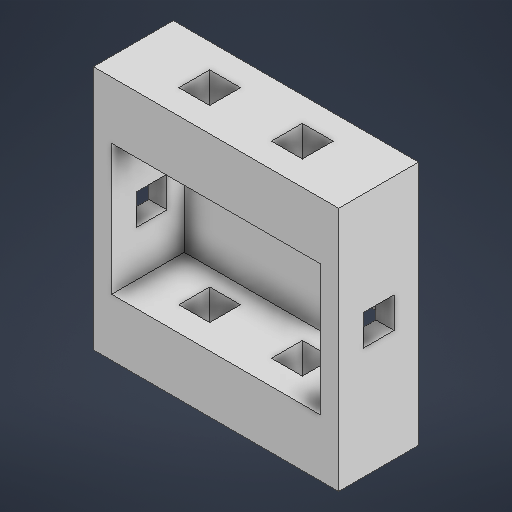
# Autodesk Inventor part: DOLNA
Saved by Autodesk Inventor 2026.1 (Build 301233020, 233B)
## iProperties
Created: 2026-09-25
Part Number: DOLNA
Material: Ogólny
Document SubType Name: Modeling
Designer: Bronh
Density: 1 g/cm^3
Appearance: Domyślna
Author: Bronh
Autodesk Inventor part; units mm, degrees
ref_plane "YZ Plane" through (0, 0, 0) normal (1, 0, 0) x (0, 1, 0)
ref_plane "XZ Plane" through (0, 0, 0) normal (0, 1, 0) x (-1, 0, 0)
ref_plane "XY Plane" through (0, 0, 0) normal (0, 0, 1) x (1, 0, 0)
sketch "Szkic1" plane through (0, 0, 0) normal (0, 0, 1) x (1, 0, 0)
  line L0 (0, 0) -> (135, 0)
  line L1 (135, 0) -> (135, 135)
  line L2 (135, 135) -> (0, 135)
  line L3 (0, 135) -> (0, 0)
  dimension "d0" = 135
  dimension "d1" = 135
  constraints: 8 end point, 2 parallel, 1 horizontal, 1 perpendicular
  measures "d0" distance of L2.end L1.end
  measures "d1" distance of L1.end L0.end
extrude "Wyciągnięcie proste1" add sketch "Szkic1" along normal blind 44
sketch "Szkic2" plane through (0, 0, 44) normal (0, 0, 1) x (1, 0, 0)
  line L0 (125, 103.5) -> (10, 103.5)
  line L1 (10, 103.5) -> (10, 31.5)
  line L2 (10, 31.5) -> (125, 31.5)
  line L3 (125, 31.5) -> (125, 103.5)
  line L4 (0, 135) -> (0, 0) projected
  line L5 (135, 135) -> (0, 135) projected
  dimension "d4" = 115
  dimension "d5" = 72
  dimension "d6" = 10
  dimension "d7" = 31.5
  constraints: 8 end point, 2 parallel, 1 horizontal, 1 perpendicular
  measures "d4" distance of L2.end L1.end
  measures "d5" distance of L1.end L0.end
  measures "d6" distance between parallel lines of L4 L1
  measures "d7" distance between parallel lines of L5 L0
extrude "Wyciągnięcie proste2" cut sketch "Szkic2" against normal blind 40
sketch "Szkic3" plane through (0, 0, 4) normal (0, 0, 1) x (1, 0, 0)
  line L0 (120, 56.5) -> (100, 56.5)
  line L1 (100, 56.5) -> (100, 36.5)
  line L2 (100, 36.5) -> (120, 36.5)
  line L3 (120, 36.5) -> (120, 56.5)
  line L4 (125, 31.5) -> (10, 31.5) projected
  line L5 (125, 103.5) -> (125, 31.5) projected
  point P0 (0, 0)
  dimension "d10" = 20
  dimension "d11" = 20
  dimension "d12" = 5
  dimension "d13" = 5
  constraints: 8 end point, 2 parallel, 1 horizontal, 1 perpendicular
  measures "d10" distance of L2.end L1.end
  measures "d11" distance of L1.end L0.end
  measures "d12" distance between parallel lines of L4 L2
  measures "d13" distance between parallel lines of L5 L3
extrude "Wyciągnięcie proste3" cut sketch "Szkic3" against normal blind 5
sketch "Szkic4" plane through (0, 0, 0) normal (0, -1, 0) x (1, 0, 0)
  line L0 (33.5, 30.5) -> (50.5, 30.5)
  line L1 (50.5, 30.5) -> (50.5, 13.5)
  line L2 (50.5, 13.5) -> (33.5, 13.5)
  line L3 (33.5, 13.5) -> (33.5, 30.5)
  line L4 (0, 44) -> (135, 44) projected
  line L5 (0, 0) -> (0, 44) projected
  point P0 (42, 30.5)
  point P1 (33.5, 22)
  dimension "d16" = 17
  dimension "d17" = 17
  dimension "d18" = 13.5
  dimension "d24" = 33.5
  constraints: 8 end point, 2 midpoint, 2 parallel, 1 horizontal, 1 perpendicular
  measures "d16" distance of L1.end L2.end
  measures "d17" distance of L0.end L1.end
  measures "d18" distance from line of point (42, 30.5) L4
  measures "d24" distance from line of L5 point (33.5, 22)
extrude "Wyciągnięcie proste4" cut sketch "Szkic4" against normal blind 31.5
sketch "Szkic7" plane through (135, 0, 0) normal (1, 0, 0) x (0, 0, -1)
  line L0 (-30.5, 61.5) -> (-13.5, 61.5)
  line L1 (-13.5, 61.5) -> (-13.5, 78.5)
  line L2 (-13.5, 78.5) -> (-30.5, 78.5)
  line L3 (-30.5, 78.5) -> (-30.5, 61.5)
  line L4 (0, 135) -> (-44, 135) projected
  line L5 (-44, 135) -> (-44, 0) projected
  point P0 (0, 0)
  point P1 (-22, 78.5)
  dimension "d30" = 17
  dimension "d31" = 17
  dimension "d32" = 56.5
  dimension "d41" = 13.5
  constraints: 8 end point, 2 parallel, 1 horizontal, 1 midpoint, 1 perpendicular
  measures "d30" distance of L2.end L1.end
  measures "d31" distance of L1.end L0.end
  measures "d32" distance from line of point (-22, 78.5) L4
  measures "d41" distance between parallel lines of L3 L5
extrude "Wyciągnięcie proste6" cut sketch "Szkic7" against normal blind 29
sketch "Szkic8" plane through (0, 0, 0) normal (-1, 0, 0) x (0, 0, 1)
  line L0 (30.5, 73.5) -> (13.5, 73.5)
  line L1 (13.5, 73.5) -> (13.5, 56.5)
  line L2 (13.5, 56.5) -> (30.5, 56.5)
  line L3 (30.5, 56.5) -> (30.5, 73.5)
  line L4 (0, 0) -> (44, 0) projected
  line L5 (0, 135) -> (0, 0) projected
  dimension "d35" = 17
  dimension "d36" = 17
  dimension "d37" = 56.5
  dimension "d40" = 13.5
  constraints: 8 end point, 2 parallel, 1 horizontal, 1 perpendicular
  measures "d35" distance of L2.end L1.end
  measures "d36" distance of L1.end L0.end
  measures "d37" distance between parallel lines of L4 L2
  measures "d40" distance between parallel lines of L5 L1
extrude "Wyciągnięcie proste7" cut sketch "Szkic8" against normal blind 29
sketch "Szkic9" plane through (0, 0, 0) normal (0, -1, 0) x (1, 0, 0)
  line L0 (84.5, 30.5) -> (101.5, 30.5)
  line L1 (101.5, 30.5) -> (101.5, 13.5)
  line L2 (101.5, 13.5) -> (84.5, 13.5)
  line L3 (84.5, 13.5) -> (84.5, 30.5)
  line L4 (0, 44) -> (135, 44) projected
  line L5 (135, 0) -> (135, 44) projected
  point P0 (0, 0)
  dimension "d42" = 17
  dimension "d43" = 17
  dimension "d44" = 13.5
  dimension "d45" = 33.5
  constraints: 8 end point, 2 parallel, 1 horizontal, 1 perpendicular
  measures "d42" distance of L1.end L2.end
  measures "d43" distance of L0.end L1.end
  measures "d44" distance between parallel lines of L0 L4
  measures "d45" distance between parallel lines of L5 L1
extrude "Wyciągnięcie proste8" cut sketch "Szkic9" against normal blind 31.5
sketch "Szkic10" plane through (0, 135, 0) normal (0, 1, 0) x (1, 0, 0)
  line L0 (101.5, -30.5) -> (84.5, -30.5)
  line L1 (84.5, -30.5) -> (84.5, -13.5)
  line L2 (84.5, -13.5) -> (101.5, -13.5)
  line L3 (101.5, -13.5) -> (101.5, -30.5)
  line L4 (135, 0) -> (135, -44) projected
  line L5 (135, -44) -> (0, -44) projected
  point P0 (0, 0)
  point P1 (135, -22)
  point P2 (93, -30.5)
  dimension "d48" = 17
  dimension "d49" = 17
  dimension "d50" = 33.5
  dimension "d51" = 13.5
  constraints: 8 end point, 2 midpoint, 2 parallel, 1 horizontal, 1 perpendicular
  measures "d48" distance of L1.end L2.end
  measures "d49" distance of L0.end L1.end
  measures "d50" distance from line of point (135, -22) L3
  measures "d51" distance from line of point (93, -30.5) L5
extrude "Wyciągnięcie proste9" cut sketch "Szkic10" against normal blind 31.5
sketch "Szkic11" plane through (0, 135, 0) normal (0, 1, 0) x (1, 0, 0)
  line L0 (50.5, -30.5) -> (33.5, -30.5)
  line L1 (33.5, -30.5) -> (33.5, -13.5)
  line L2 (33.5, -13.5) -> (50.5, -13.5)
  line L3 (50.5, -13.5) -> (50.5, -30.5)
  line L4 (135, -44) -> (0, -44) projected
  line L5 (0, 0) -> (0, -44) projected
  point P0 (42, -30.5)
  dimension "d54" = 17
  dimension "d55" = 17
  dimension "d56" = 13.5
  dimension "d57" = 33.5
  constraints: 8 end point, 2 parallel, 1 horizontal, 1 midpoint, 1 perpendicular
  measures "d54" distance of L1.end L2.end
  measures "d55" distance of L0.end L1.end
  measures "d56" distance from line of point (42, -30.5) L4
  measures "d57" distance between parallel lines of L5 L1
extrude "Wyciągnięcie proste10" cut sketch "Szkic11" against normal blind 31.5
